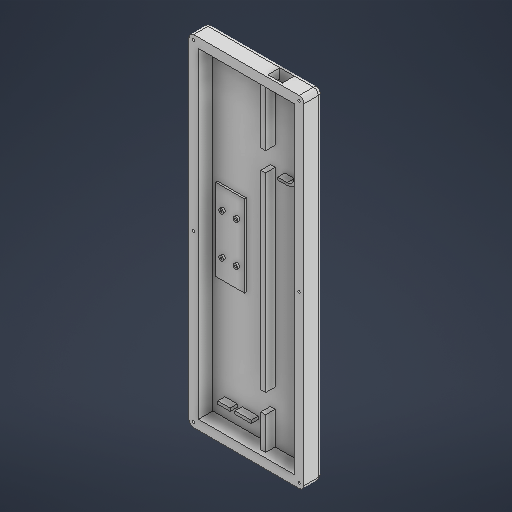
# Autodesk Inventor part: Parte trasera
Saved by Autodesk Inventor 2027 (Build 310192060, 192F)
## iProperties
Created: 2026-02-11
Part Number: Parte trasera
Material: Genérico
Document SubType Name: Modeling
Designer: Pablo
Density: 1 g/cm^3
Appearance: Valor por defecto
Author: Pablo
Autodesk Inventor part; units mm, degrees
ref_plane "YZ Plane" through (0, 0, 0) normal (1, 0, 0) x (0, 1, 0)
ref_plane "XZ Plane" through (0, 0, 0) normal (0, 1, 0) x (-1, 0, 0)
ref_plane "XY Plane" through (0, 0, 0) normal (0, 0, 1) x (1, 0, 0)
sketch "Boceto1" plane through (0, 0, 0) normal (0, 0, 1) x (1, 0, 0)
  line L0 (0, 279.8883) -> (0, -279.8883)
  line L1 (-153.0726, 0) -> (153.0726, 0)
  line L2 (-100, 335) -> (100, 335)
  line L3 (100, 335) -> (100, -335)
  line L4 (100, -335) -> (-100, -335)
  line L5 (-100, -335) -> (-100, 335)
  line L6 (-120, 355) -> (120, 355)
  line L7 (120, 355) -> (120, -355)
  line L8 (120, -355) -> (-120, -355)
  line L9 (-120, -355) -> (-120, 355)
  line L10 (40, 355) -> (40, 335)
  line L11 (70, 355) -> (70, 335)
  line L12 (-110, 345) -> (-110, -345)
  line L13 (-110, -345) -> (110, -345)
  line L14 (110, -345) -> (110, 345)
  line L15 (110, 345) -> (-110, 345)
  circle A0 centre (-110, 345) radius 2.5
  circle A1 centre (110, 345) radius 2.5
  circle A2 centre (110, 0) radius 2.5
  circle A3 centre (110, -345) radius 2.5
  circle A4 centre (-110, -345) radius 2.5
  circle A5 centre (-110, 0) radius 2.5
  line L16 (-100, 309.5) -> (37, 309.5)
  line L17 (37, 309.5) -> (37, -309.5)
  line L18 (37, -309.5) -> (-100, -309.5)
  line L19 (-100, -309.5) -> (-100, 309.5)
  line L20 (-31.5, 316.3518) -> (-31.5, -305.1898)
  line L21 (-105, 316.3518) -> (42, 316.3518)
  line L22 (42, 316.3518) -> (42, -316.3518)
  line L23 (42, -316.3518) -> (-105, -316.3518)
  line L24 (-105, -316.3518) -> (-105, 316.3518)
  line L25 (37, 282.283) -> (42, 282.283)
  line L26 (37, 257.283) -> (42, 257.283)
  point P0 (0, 0)
  point P1 (0, 0)
  point P2 (0, 335)
  point P3 (100, 0)
  point P4 (0, 355)
  point P5 (120, 0)
  point P6 (37, 0)
  point P7 (-31.5, 309.5)
  point P8 (42, 0)
  dimension "d0" = 200
  dimension "d1" = 670
  dimension "d2" = 20
  dimension "d3" = 20
  dimension "d4" = 30
  dimension "d5" = 40
  dimension "d7" = 5
  dimension "d8" = 5
  dimension "d9" = 5
  dimension "d10" = 5
  dimension "d11" = 5
  dimension "d12" = 5
  dimension "d22" = 5
  dimension "d23" = 619
  dimension "d24" = 137
  dimension "d25" = 0
  dimension "d27" = 25
  constraints: 55 end point, 16 point on line, 12 midpoint, 9 horizontal, 8 parallel, 6 centre point, 6 vertical, 5 coincident, 4 perpendicular, 4 other
  measures "d0" distance between parallel lines of L3 L5
  measures "d1" distance between parallel lines of L4 L2
  measures "d2" distance between parallel lines of L2 L6
  measures "d3" distance between parallel lines of L7 L3
  measures "d4" distance between parallel lines of L10 L11
  measures "d5" distance between parallel lines of L10 L0
  measures "d7" diameter of A0
  measures "d8" diameter of A1
  measures "d9" diameter of A2
  measures "d10" diameter of A3
  measures "d11" diameter of A4
  measures "d12" diameter of A5
  measures "d22" distance between parallel lines of L17 L22
  measures "d23" distance between parallel lines of L18 L16
  measures "d24" distance between parallel lines of L17 L19
  measures "d25" distance between parallel lines of L5 L19
  measures "d27" distance between parallel lines of L26 L25
extrude "Extrusión1" add sketch "Boceto1" along normal blind 40 contours L9 L6 L10 L15 A0 L12 A5 L1 | L1 A5 L12 A4 L13 A3 L14 A2 L7 L8 L9 | A5 L12 L1 | L1 L12 A5 | L12 A5 L1 | L1 A5 L12 | L12 A0 L15 L10 L2 L5 L21 L24 L1 A5 | A5 L1 L24 L23 L5 L4 L3 A2 L14 A3 L13 A4 L12 | L6 L11 L15 L10 | A0 L15 L12 | L12 L15 A0 | A4 L13 L12 | L12 L13 A4 | L1 A2 L14 A1 L15 L11 L6 L7 | L15 L11 L2 L10 | L24 L21 L5 L1 | L1 L5 L23 L24 | A2 L14 L1 | L1 L14 A2 | L15 A1 L14 A2 L1 L3 L2 L11 | A3 L14 L13 | L13 L14 A3 | L14 A2 L1 | L1 A2 L14 | A1 L14 L15 | L15 L14 A1
extrude "Extrusión2" add sketch "Boceto1" along normal blind 10 contours L2 L3 L1 L22 L21 L5 | L5 L16 L20 L1 | L1 L17 L18 L5 | L20 L16 L17 L1 | L18 L17 L1 L22 L23 L5 | L5 L21 L20 L16 | L23 L22 L1 L3 L4 L5 | L20 L21 L22 L25 L17 L16 | L17 L26 L22 L1 | L17 L25 L22 L26
extrude "Extrusión3" cut sketch "Boceto1" along normal blind 25 from surface at 10 contours L6 L11 L15 L10 | L15 L11 L2 L10
fillet "Empalme1" radius 10 8 edges at (120, 355, 20) (-120, 355, 20) (120, -355, 20) (-120, -355, 20) (0, 355, 0) (-120, 0, 0) (120, 0, 0) (0, -355, 0)
extrude "Extrusión4" cut sketch "Boceto1" along normal through all contours A5 L12 L1 | L1 L12 A5 | L12 A5 L1 | L1 A5 L12 | A0 L15 L12 | L12 L15 A0 | A4 L13 L12 | L12 L13 A4 | A2 L14 L1 | L1 L14 A2 | A3 L14 L13 | L13 L14 A3 | L14 A2 L1 | L1 A2 L14 | A1 L14 L15 | L15 L14 A1
sketch "Sketch2" plane through (0, 0, 10) normal (0, 0, 1) x (1, 0, 0)
  line L0 (-100, -335) -> (-100, 335) construction
  line L1 (-100, 335) -> (100, 335) construction
  line L2 (100, 335) -> (100, -335) construction
  line L3 (100, -335) -> (-100, -335) construction
  line L4 (-90, -85) -> (-30, -85)
  line L5 (-30, -85) -> (-30, 85)
  line L6 (-30, 85) -> (-90, 85)
  line L7 (-90, 85) -> (-90, -85)
  line L8 (-90, -85) -> (-30, 85) construction
  line L9 (-30, -85) -> (-90, 85) construction
  line L10 (0, 0) -> (-60, 0) construction
  circle A0 centre (-75, 42.5) radius 5
  circle A1 centre (-75, 42.5) radius 2
  line L11 (-60, 0) -> (-60, 42.9576)
  line L12 (-60, 0) -> (-78.6912, 0)
  circle A2 centre (-45, 42.5) radius 5
  circle A3 centre (-45, 42.5) radius 2
  circle A4 centre (-75, -42.5) radius 5
  circle A5 centre (-75, -42.5) radius 2
  circle A6 centre (-45, -42.5) radius 5
  circle A7 centre (-45, -42.5) radius 2
  dimension "d30" = 60
  dimension "d31" = 60
  dimension "d32" = 170
  dimension "d33" = 10
  dimension "d34" = 4
  dimension "d35" = 30
  constraints: 18 end point, 8 centre point, 6 symmetric about line, 4 coincident, 3 horizontal, 2 midpoint, 2 parallel, 1 perpendicular, 1 point on line, 1 vertical, 6 other
  measures "d30" distance of L10.start L10.end
  measures "d31" distance of L5.end L6.end
  measures "d32" distance of L6.end L4.start
  measures "d33" diameter of A0
  measures "d34" diameter of A1
  measures "d35" distance of A2.centre A0.centre
extrude "Extrusion6" add sketch "Sketch2" along normal blind 4 contours L7 L6 L5 L4
extrude "Extrusion7" add sketch "Sketch2" along normal blind 8 contours A0 | A2 | A4 | A6
sketch "Sketch3" plane through (0, 0, 10) normal (0, 0, 1) x (1, 0, 0)
  line L0 (100, -335) -> (-100, -335) projected
  line L1 (-100, 335) -> (100, 335) projected
  line L2 (30, 335) -> (30, -335)
  line L3 (20, -335) -> (20, 335)
  line L4 (100, -335) -> (-100, -335) projected
  line L5 (20, -226.7583) -> (30, -226.7583)
  line L6 (20, -266.7583) -> (30, -266.7583)
  line L7 (20, 210.119) -> (30, 210.119)
  line L8 (20, 170.119) -> (30, 170.119)
  point P0 (0, 0)
  dimension "d40" = 10
  dimension "d41" = 40
  dimension "d42" = 40
  dimension "d43" = 20
  constraints: 12 end point, 12 point on line, 5 perpendicular, 1 vertical
  measures "d40" distance between parallel lines of L2 L3
  measures "d41" distance between parallel lines of L8 L7
  measures "d42" distance between parallel lines of L6 L5
  measures "d43" distance from line of L3 point (0, 0)
extrude "Extrusion8" add sketch "Sketch3" along normal blind 20 contours L0 L3 L6 L2 | L5 L3 L8 L2 | L7 L3 L1 L2
sketch "Sketch4" plane through (0, 0, 10) normal (0, 0, 1) x (1, 0, 0)
  line L0 (-75, -296.7583) -> (-5, -296.7583)
  line L1 (-5, -296.7583) -> (-5, -302.7583)
  line L2 (-5, -302.7583) -> (-75, -302.7583)
  line L3 (-75, -302.7583) -> (-75, -296.7583)
  line L4 (20, -335) -> (20, -266.7583) construction
  line L5 (-48.9626, -296.7583) -> (-48.9626, -302.7583)
  line L6 (-38.9626, -296.7583) -> (-38.9626, -302.7583)
  point P0 (0, 0)
  dimension "d46" = 6
  dimension "d47" = 70
  dimension "d48" = 25
  dimension "d49" = 30
  dimension "d50" = 10
  constraints: 12 end point, 4 perpendicular, 4 point on line, 1 horizontal, 1 vertical
  measures "d46" distance between parallel lines of L2 L0
  measures "d47" distance of L0.start L0.end
  measures "d48" distance between parallel lines of L4 L1
  measures "d49" distance from line of L0 L4.end
  measures "d50" distance between parallel lines of L6 L5
extrude "Extrusion9" add sketch "Sketch4" along normal blind 15 contours L0 L5 L2 L3 | L0 L1 L2 L6
sketch "Sketch5" plane through (0, 0, 10) normal (0, 0, 1) x (1, 0, 0)
  line L0 (85, 215) -> (85, 185)
  line L1 (70, 170) -> (50, 170)
  line L2 (50, 170) -> (50, 165)
  line L3 (50, 165) -> (70, 165)
  line L4 (90, 185) -> (90, 215)
  line L5 (90, 215) -> (85, 215)
  arc A0 (70, 170) -> (85, 185) centre (70, 185) ccw
  arc A1 (70, 165) -> (90, 185) centre (70, 185) ccw
  point P0 (0, 0)
  dimension "d53" = 5
  dimension "d54" = 5
  dimension "d55" = 15
  dimension "d56" = 20
  dimension "d57" = 20
  dimension "d58" = 70
  dimension "d59" = 30
  dimension "d60" = 185
  constraints: 12 end point, 4 perpendicular, 4 point on circle, 4 tangent, 2 centre point, 1 parallel, 1 vertical
  measures "d53" distance between parallel lines of L4 L0
  measures "d54" distance of L1.end L2.end
  measures "d55" radius of A0
  measures "d56" radius of A1
  measures "d57" distance from line of L2 A0.centre
  measures "d58" horizontal distance of point (0, 0) A0.centre
  measures "d59" distance from line of A0.centre L5
  measures "d60" vertical distance of point (0, 0) A0.centre
extrude "Extrusion10" add sketch "Sketch5" along normal blind 15
